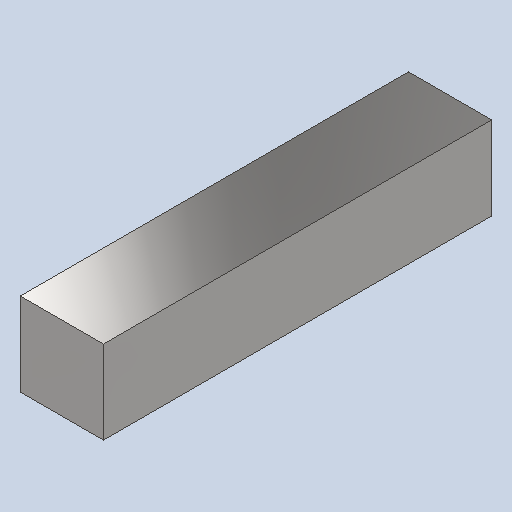
# Autodesk Inventor part: DIN 6885-B 3x3x14
Saved by Autodesk Inventor 2025.3 (Build 293356000, 356)
## iProperties
Created: 2026-11-06
Part Number: DIN 6885-B 3x3x14
Material: Acier, carbone
Document SubType Name: Modeling
Designer: hugoh
Density: 7.85 g/cm^3
Appearance: Semi-poli
Author: hugoh
Autodesk Inventor part; units mm, degrees
ref_plane "YZ Plane" through (0, 0, 0) normal (1, 0, 0) x (0, 1, 0)
ref_plane "XZ Plane" through (0, 0, 0) normal (0, 1, 0) x (-1, 0, 0)
ref_plane "XY Plane" through (0, 0, 0) normal (0, 0, 1) x (1, 0, 0)
sketch "Esquisse1" plane through (0, 0, 0) normal (0, 1, 0) x (-1, 0, 0)
  line L0 (1.5, 7) -> (-1.5, 7)
  line L1 (-1.5, 7) -> (-1.5, -7)
  line L2 (-1.5, -7) -> (1.5, -7)
  line L3 (1.5, -7) -> (1.5, 7)
  line L4 (1.5, 7) -> (-1.5, -7) construction
  line L5 (-1.5, 7) -> (1.5, -7) construction
  point P0 (0, 0)
  dimension "d0" = 14
  dimension "d1" = 3
  constraints: 12 end point, 2 midpoint, 2 parallel, 1 horizontal, 1 perpendicular
  measures "d0" distance of L2.end L0.start
  measures "d1" distance of L1.end L2.end
extrude "Extrusion1" add sketch "Esquisse1" along normal blind 3
